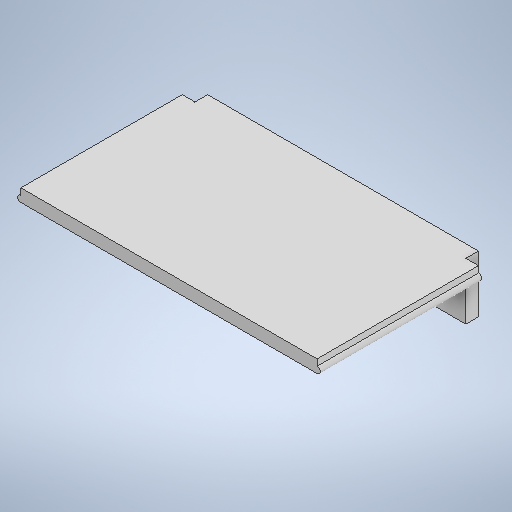
# Autodesk Inventor part: arm motor cover
Saved by Autodesk Inventor 2025.3 (Build 293356000, 356)
## iProperties
Created: 2025-09-24
Part Number: arm motor cover
Material: Generic
Document SubType Name: Modeling
Designer: kuusela
Density: 1 g/cm^3
Appearance: Default
Author: kuusela
## iProperties of the stored document arm motor cover_3DPrint.ipt
Created: 2025-10-14
Part Number: arm motor cover_3DPrint
Material: Generic
Document SubType Name: Modeling
Designer: kuuse
Density: 1 g/cm^3
Appearance: Default
Author: kuuse
Autodesk Inventor part; units mm, degrees
ref_plane "YZ Plane" through (0, 0, 0) normal (1, 0, 0) x (0, 1, 0)
ref_plane "XZ Plane" through (0, 0, 0) normal (0, 1, 0) x (-1, 0, 0)
ref_plane "XY Plane" through (0, 0, 0) normal (0, 0, 1) x (1, 0, 0)
sketch "Sketch1" plane through (0, 0, 0) normal (0, 0, 1) x (1, 0, 0)
  line L0 (-13.25, 22.9) -> (33.55, 22.9)
  line L1 (33.55, 22.9) -> (33.55, 20.9)
  line L2 (33.55, 20.9) -> (-13.25, 20.9)
  line L3 (-13.25, 20.9) -> (-13.25, 22.9)
  arc A0 (-13.25, 21.9) -> (-13.25, 20.9) centre (-13.25, 21.4) ccw
  arc A1 (33.55, 20.9) -> (33.55, 21.9) centre (33.55, 21.4) ccw
  line L4 (31.55, 20.9) -> (31.55, 13.9)
  line L5 (31.55, 13.9) -> (-11.25, 13.9)
  line L6 (-11.25, 13.9) -> (-11.25, 20.9)
  line L7 (31.55, 20.9) -> (31.55, 22.9)
  line L8 (-11.25, 20.9) -> (-11.25, 22.9)
  point P0 (0, 0)
  dimension "d0" = 2
  dimension "d1" = 0.5
  dimension "d5" = 2
  dimension "d6" = 2
  dimension "d7" = 9
  dimension "d12" = 42.8
  constraints: 18 end point, 6 perpendicular, 4 point on circle, 4 point on line, 2 centre point, 2 midpoint, 2 tangent, 1 horizontal, 1 parallel, 1 vertical
  measures "d0" distance between parallel lines of L0 L2
  measures "d1" radius of A1
  measures "d5" distance between parallel lines of L3 L6
  measures "d6" distance between parallel lines of L4 L1
  measures "d7" distance between parallel lines of L0 L5
  measures "d12" distance between parallel lines of L6 L4
extrude "Extrusion1" add sketch "Sketch1" along normal blind 2 contours L0 L7 L2 L8 | L2 L4 L5 L6
extrude "Extrusion2" add sketch "Sketch1" along normal blind 27.5 contours L0 L7 L2 L8
extrude "Extrusion3" add sketch "Sketch1" against normal blind 25.5 from surface at 27.5 contours L0 L8 L2 L3 | L3 A0 | L0 L1 L2 L7 | A1 L1
body "Solid1"
